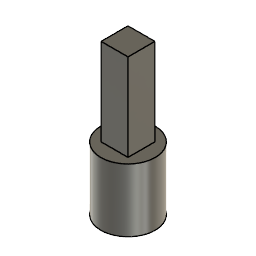
Small bevel coupling (Autodesk Fusion 360 design; units mm, degrees)
Autodesk Fusion 360 part; units mm, degrees
sketch "Sketch1" plane through (0, 0, 0) normal (0, 0, 1) x (1, 0, 0)
  line L0 (-1.397, 1.6995) -> (1.397, 1.6995)
  arc A0 (-1.397, 1.6995) -> (1.397, 1.6995) centre (0, 0) ccw
  circle A1 centre (0, 0) radius 3.175
  dimension "d1" = 4.4
  dimension "d2" = 2.794
  dimension "d8" = 3.175
  constraint coincident A0.centre A1.centre
  constraint horizontal L0
  constraint concentric A0 A1
  measures "d1" diameter of A0
  measures "d2" distance of L0.start L0.end
  measures "d8" radius of A1
extrude "Extrude1" add sketch "Sketch1" along normal blind 6.35
sketch "Sketch4" plane through (0, 0, 6.35) normal (0, 0, 1) x (-1, 0, 0)
  arc A0 (1.397, -1.6995) -> (-1.397, -1.6995) centre (0, 0) ccw
  line L0 (1.397, -1.6995) -> (-1.397, -1.6995)
  circle A1 centre (0, 0) radius 3.175
  circle A2 centre (0, 0) radius 3.175
  dimension "d9" = 6.35
  constraint coincident A0.centre A1.centre
  measures "d9" diameter of A2
extrude "Extrude2" add sketch "Sketch4" along normal blind 1.016 contours A0 L0 | A1 A2
sketch "Sketch5" plane through (0, 0, 7.366) normal (0, 0, 1) x (-1, 0, 0)
  circle A0 centre (0, 0) radius 3.175
  line L0 (-1.5748, -1.5748) -> (1.5748, -1.5748)
  line L1 (1.5748, -1.5748) -> (1.5748, 1.5748)
  line L2 (1.5748, 1.5748) -> (-1.5748, 1.5748)
  line L3 (-1.5748, 1.5748) -> (-1.5748, -1.5748)
  line L4 (-1.5748, -1.5748) -> (1.5748, 1.5748) construction
  line L5 (1.5748, -1.5748) -> (-1.5748, 1.5748) construction
  dimension "d12" = 3.1496
  dimension "d13" = 3.1496
  constraint horizontal L0
  constraint perpendicular L0 L1
  constraint parallel L0 L2
  constraint parallel L1 L3
  constraint coincident L4 A0.centre
  constraint coincident L5 A0.centre
  constraint coincident A0.centre origin
  measures "d12" distance of L0.end L1.end
  measures "d13" distance of L0.start L0.end
extrude "Extrude3" add sketch "Sketch5" along normal blind 10.16 contours L0 L1 L2 L3
